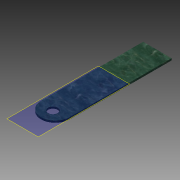
# Autodesk Inventor part: Yaw_Side2
Saved by Autodesk Inventor 2013 (Build 170138000, 138)
## iProperties
Created: 2013-09-30
Part Number: Yaw_Side2
Material: Generic
Document SubType Name: Modeling
Designer: Jeff
Density: 1 g/cm^3
Author: Jeff
Autodesk Inventor part; units mm, degrees
ref_plane "YZ Plane" through (0, 0, 0) normal (1, 0, 0) x (0, 1, 0)
ref_plane "XZ Plane" through (0, 0, 0) normal (0, 1, 0) x (-1, 0, 0)
ref_plane "XY Plane" through (0, 0, 0) normal (0, 0, 1) x (1, 0, 0)
ref_plane "Work Plane1" through (0, 0, -1.5875) normal (0, 0, -1) x (-1, 0, 0)
sketch "Sketch1" plane through (0, 0, -1.5875) normal (0, 0, -1) x (-1, 0, 0)
  circle A0 centre (0, -16.9798) radius 4 projected
  line L0 (0, -36.9798) -> (0, -36.9798)
  line L1 (-12, -24.9798) -> (-12, 21.0202)
  arc A1 (-12, -24.9798) -> (0, -36.9798) centre (0, -24.9798) ccw
  line L2 (12, -24.9798) -> (12, 21.0202)
  arc A2 (0, -36.9798) -> (12, -24.9798) centre (0, -24.9798) ccw
  line L3 (-12, 61.0202) -> (12, 61.0202) projected
  line L4 (-12, 21.0202) -> (-12, 61.0202)
  line L5 (12, 61.0202) -> (12, 21.0202)
  point P0 (0, 0)
  point P1 (12, -36.9798)
  dimension "d3" = 12
  dimension "d4" = 12
  dimension "d7" = 8
  constraints: 10 end point, 5 point on circle, 4 tangent, 2 centre point, 2 point on line, 1 parallel
  measures "d3" radius of A1
  measures "d4" radius of A2
  measures "d7" diameter of A0
extrude "Extrusion2" add sketch "Sketch1" along normal blind 1.5875
body "Solid2"
